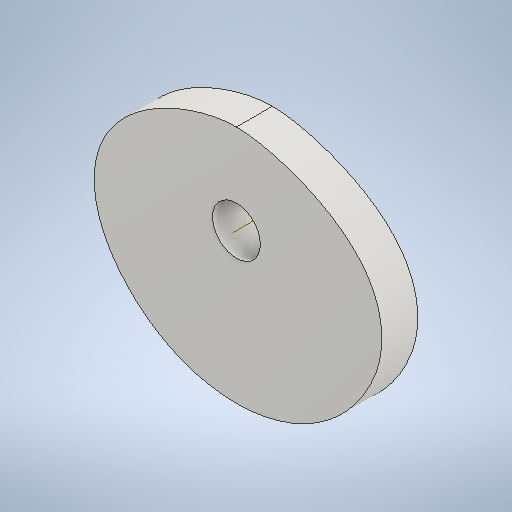
# Autodesk Inventor part: Disc Cam
Saved by Autodesk Inventor 2025.2 (Build 292293000, 293)
## iProperties
CustomPartVersion: 1
Created: 2025-05-16
Part Number: Disc Cam
Material: Stainless Steel, Austenitic
Document SubType Name: Modeling
Designer: laura
Manufacturer: Standard
Standards Organization: Custom
Density: 1 g/cm^3
Appearance: Steel
Author: laura
Autodesk Inventor part; units mm, degrees
ref_plane "YZ Plane" through (0, 0, 0) normal (1, 0, 0) x (0, 1, 0)
ref_plane "XZ Plane" through (0, 0, 0) normal (0, 1, 0) x (-1, 0, 0)
ref_plane "XY Plane" through (0, 0, 0) normal (0, 0, 1) x (1, 0, 0)
sketch "Main Sketch" plane through (0, 0, 0) normal (0, 0, 1) x (1, 0, 0)
  spline S0 degree 5 poles (0, 15) (0.4138, 15) (1.115, 14.9773) (2.2011, 14.8848) (3.7654, 14.659) (5.7557, 14.2218) (7.7539, 13.6682) (9.8513, 12.9566) (11.9493, 12.1116) (13.9995, 11.1328) (15.965, 10.0158) (17.8033, 8.7577) (19.4766, 7.3562) (20.9321, 5.8256) (22.1559, 4.1546) (23.1275, 2.3507) (23.8301, 0.4251) (24.2477, -1.6055) (24.3654, -3.7232) (24.1718, -5.9042) (23.6562, -8.1271) (22.8254, -10.3556) (21.6725, -12.5915) (20.2583, -14.7652) (18.6234, -16.7794) (16.7724, -18.6316) (14.7352, -20.2806) (12.5342, -21.7102) (10.1964, -22.9013) (7.7466, -23.8417) (5.2121, -24.5208) (2.6204, -24.9313) (0, -25.0686) (-2.6204, -24.9313) (-5.212, -24.5208) (-7.7467, -23.8417) (-10.1963, -22.9014) (-12.534, -21.7103) (-14.7303, -20.2839) (-16.761, -18.6408) (-18.5935, -16.8101) (-20.2245, -14.8113) (-21.5544, -12.7509) (-22.5914, -10.6142) (-23.3144, -8.4424) (-23.7252, -6.2599) (-23.8261, -4.0985) (-23.6267, -1.985) (-23.1392, 0.055) (-22.3798, 1.9989) (-21.3658, 3.8301) (-20.1197, 5.5348) (-18.658, 7.1174) (-17.0216, 8.5636) (-15.2472, 9.8678) (-13.3692, 11.0291) (-11.422, 12.0484) (-9.436, 12.926) (-7.4507, 13.66) (-5.5541, 14.2245) (-3.6539, 14.6644) (-2.148, 14.8877) (-1.095, 14.9779) (-0.4081, 15) (0, 15) knots 0 0 0 0 0 0 0.01785 0.030178 0.045815 0.061921 0.078331 0.094906 0.111528 0.128097 0.144526 0.160766 0.176812 0.19269 0.208466 0.224234 0.240091 0.256127 0.272431 0.289092 0.306134 0.323504 0.341129 0.358921 0.376773 0.394626 0.412478 0.43033 0.448182 0.466034 0.483887 0.501739 0.519591 0.537443 0.555296 0.573148 0.591 0.608852 0.626683 0.644408 0.661951 0.679247 0.696244 0.71292 0.729329 0.745528 0.761572 0.777522 0.793439 0.809393 0.825434 0.841588 0.857854 0.874207 0.89059 0.906938 0.923177 0.93922 0.954965 0.970294 0.982393 1 1 1 1 1 1
  point P0 (3.5656, 14.6591)
  point P1 (5.5788, 14.2366)
  point P2 (7.6748, 13.6599)
  point P3 (9.8052, 12.94)
  point P4 (11.925, 12.0834)
  point P5 (13.9926, 11.0906)
  point P6 (15.9679, 9.9586)
  point P7 (17.8093, 8.6858)
  point P8 (19.4702, 7.2788)
  point P9 (20.9074, 5.751)
  point P10 (22.108, 4.098)
  point P11 (23.0611, 2.3194)
  point P12 (23.7522, 0.4238)
  point P13 (24.1663, -1.575)
  point P14 (24.2891, -3.6598)
  point P15 (24.1079, -5.8114)
  point P16 (23.6124, -8.0113)
  point P17 (22.795, -10.2439)
  point P18 (21.6506, -12.5)
  point P19 (20.2254, -14.6946)
  point P20 (18.5786, -16.7283)
  point P21 (16.7283, -18.5786)
  point P22 (14.6946, -20.2254)
  point P23 (12.5, -21.6506)
  point P24 (10.1684, -22.8386)
  point P25 (7.7254, -23.7764)
  point P26 (5.1978, -24.4537)
  point P27 (2.6132, -24.863)
  point P28 (0, -25)
  point P29 (-2.6132, -24.863)
  point P30 (-5.1978, -24.4537)
  point P31 (-7.7254, -23.7764)
  point P32 (-10.1684, -22.8386)
  point P33 (-12.5, -21.6506)
  point P34 (-14.6946, -20.2254)
  point P35 (-16.7283, -18.5786)
  point P36 (-18.5786, -16.7283)
  point P37 (-20.2053, -14.7185)
  point P38 (-21.5316, -12.6418)
  point P39 (-22.5492, -10.5164)
  point P40 (-23.2567, -8.3619)
  point P41 (-23.6553, -6.2024)
  point P42 (-23.7502, -4.0647)
  point P43 (-23.5503, -1.9754)
  point P44 (-23.0685, 0.0407)
  point P45 (-22.3202, 1.9628)
  point P46 (-21.3222, 3.7762)
  point P47 (-20.0906, 5.4743)
  point P48 (-18.6405, 7.0576)
  point P49 (-17.0064, 8.5124)
  point P50 (-15.2284, 9.8271)
  point P51 (-13.3429, 10.9985)
  point P52 (-11.3834, 12.0268)
  point P53 (-9.3824, 12.9116)
  point P54 (-7.3734, 13.6501)
  point P55 (-5.3916, 14.2358)
  point P56 (-3.4743, 14.6602)
  point P57 (-1.6622, 14.9158)
  constraints: 60 other
extrude "Cam" add sketch "Main Sketch" along normal blind 6
sketch "Sketch2" plane through (0, 0, 6) normal (0, 0, 1) x (1, 0, 0)
  circle A0 centre (0, 0) radius 4
  dimension "d4" = 8
  constraints: 1 centre point, 1 coincident
  measures "d4" diameter of A0
extrude "Extrusion2" cut sketch "Sketch2" against normal through all
body "Solid1"
